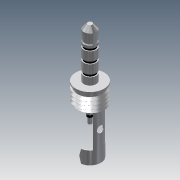
# Autodesk Inventor part: 3.5mm Plug
Saved by Autodesk Inventor 2013 SP2 (Build 170200200, 200)
## iProperties
Created: 2018-02-05
Part Number: 3.5mm Plug
Material: Generic
Document SubType Name: Modeling
Designer: ctouchatt
Density: 1 g/cm^3
Author: ctouchatt
Autodesk Inventor part; units mm, degrees
ref_plane "XZ Plane" through (0, 0, 0) normal (0, 1, 0) x (-1, 0, 0)
sketch "Sketch1" plane through (0, 0, 0) normal (0, 1, 0) x (-1, 0, 0)
  circle A0 centre (0, 0) radius 4.0005
  dimension "d0" = 8.001
  constraints: 1 centre point, 1 coincident
  measures "d0" diameter of A0
extrude "Extrusion1" add sketch "Sketch1" along normal blind 5.2832
sketch "Sketch2" plane through (0, 5.2832, 0) normal (0, 1, 0) x (1, 0, 0)
  circle A0 centre (0, 0) radius 4.0005 projected
  circle A1 centre (0, 0) radius 1.75
  dimension "d3" = 3.5
  constraints: 1 centre point, 1 coincident
  measures "d3" diameter of A1
extrude "Extrusion2" add sketch "Sketch2" along normal blind 14 contours A1
sketch "Sketch3" plane through (0, 0, 0) normal (0, 0, 1) x (1, 0, 0)
  line L0 (1.75, 19.2832) -> (-1.75, 19.2832) projected
  line L1 (-1.75, 5.2832) -> (1.75, 5.2832) projected
  line L2 (1.75, 5.2832) -> (1.75, 19.2832) projected
  line L3 (0, 19.2832) -> (0.635, 19.2832)
  line L4 (1.75, 19.2832) -> (1.75, 18.0132)
  line L5 (1.75, 18.0132) -> (0.635, 19.2832)
  line L6 (0, 19.2832) -> (0, 15.016)
  line L7 (0, 15.016) -> (1.75, 15.016) construction
  line L8 (1.75, 15.016) -> (1.5568, 15.236)
  line L9 (1.5568, 15.236) -> (1.75, 18.0132)
  line L10 (0, -3.8566) -> (0, 23.1398) projected
  line L11 (1.75, 14.3049) -> (1.496, 14.3049)
  line L12 (1.496, 14.3049) -> (1.496, 13.6699)
  line L13 (1.496, 13.6699) -> (1.75, 13.6699)
  line L14 (1.75, 13.6699) -> (1.75, 14.3049)
  line L15 (1.75, 11.1299) -> (1.496, 11.1299)
  line L16 (1.496, 11.1299) -> (1.496, 10.4949)
  line L17 (1.496, 10.4949) -> (1.75, 10.4949)
  line L18 (1.75, 10.4949) -> (1.75, 11.1299)
  line L19 (1.75, 7.9549) -> (1.496, 7.9549)
  line L20 (1.496, 7.9549) -> (1.496, 7.3199)
  line L21 (1.496, 7.3199) -> (1.75, 7.3199)
  line L22 (1.75, 7.3199) -> (1.75, 7.9549)
  line L23 (4.0005, 0) -> (4.0005, 5.2832) projected
  line L24 (-4.0005, 0) -> (4.0005, 0) projected
  line L25 (4.0005, 4.7772) -> (3.556, 4.7772)
  line L26 (3.556, 4.7772) -> (3.556, 3.7612)
  line L27 (3.556, 3.7612) -> (4.0005, 3.7612)
  line L28 (4.0005, 3.7612) -> (4.0005, 4.7772)
  point P0 (0, 0)
  dimension "d6" = 0.635
  dimension "d7" = 1.27
  dimension "d8" = 4.2672
  dimension "d11" = 0.254
  dimension "d12" = 0.635
  dimension "d15" = 0.254
  dimension "d16" = 0.635
  dimension "d17" = 2.54
  dimension "d18" = 4.9783
  dimension "d19" = 0.254
  dimension "d20" = 0.635
  dimension "d21" = 2.54
  dimension "d34" = 1.016
  dimension "d35" = 3.556
  constraints: 46 end point, 10 parallel, 5 horizontal, 4 perpendicular, 2 point on line, 1 midpoint, 6 other
  measures "d6" distance of L3.start L3.end
  measures "d7" distance of L4.start L4.end
  measures "d8" distance of L3.start L6.end
  measures "d11" distance of L13.end L12.end
  measures "d12" distance of L12.end L11.end
  measures "d15" distance of L17.end L16.end
  measures "d16" distance of L16.end L15.end
  measures "d17" distance between parallel lines of L13 L15
  measures "d18" distance between parallel lines of L0 L11
  measures "d19" distance of L21.end L20.end
  measures "d20" distance of L20.end L19.end
  measures "d21" distance between parallel lines of L17 L19
  measures "d34" distance of L25.end L26.end
  measures "d35" distance from line of point (0, 0) L26
revolve "Revolution1" cut sketch "Sketch3" angle 360 about axis through (0, -10, 0) along (0, 1, 0) contours L2 L5 L0 | L2 L8 L9 | L2 L13 L12 L11 | L2 L17 L16 L15 | L21 L20 L19 L2 | L27 L26 L25 L23
sketch "Sketch4" plane through (0, 0, 0) normal (0, -1, 0) x (1, 0, 0)
  circle A0 centre (0, 0) radius 4.0005 projected
  arc A1 (0, -3.048) -> (0, 3.048) centre (0, 0) ccw
  arc A2 (0, -2.794) -> (0, 2.794) centre (0, 0) ccw
  line L0 (0, 3.048) -> (0, 2.794)
  line L1 (0, -2.794) -> (0, -3.048)
  dimension "d22" = 6.096
  dimension "d23" = 5.588
  constraints: 4 end point, 4 point on circle, 2 centre point, 2 coincident, 1 collinear, 1 vertical
  measures "d22" diameter of A1
  measures "d23" diameter of A2
extrude "Extrusion3" add sketch "Sketch4" along normal blind 13.335 contours L1 A2 L0 A1
ref_plane "Work Plane1" through (0, 0, 3.048) normal (0, 0, 1) x (1, 0, 0)
sketch "Sketch5" plane through (0, 0, 3.048) normal (0, 0, 1) x (1, 0, 0)
  line L0 (0, 0) -> (0, 0) projected
  line L1 (0, 0) -> (0, -13.335) projected
  line L2 (0, -13.335) -> (0, -13.335) projected
  line L3 (0, 0) -> (0, -13.335) projected
  line L4 (0, -13.335) -> (3.048, -13.335) projected
  line L5 (2.794, -13.335) -> (2.794, 0) projected
  line L6 (3.048, 0) -> (3.048, -13.335) projected
  line L7 (0.49, -9.7028) -> (2.54, -9.7028)
  line L8 (2.54, -9.7028) -> (2.54, 0)
  line L9 (2.54, 0) -> (0, 0)
  line L10 (0, 0) -> (0, -9.7028)
  line L11 (0, -11.5314) -> (0.49, -9.7028)
  line L12 (0, -11.5314) -> (1.8931, -11.5314) construction
  line L13 (0, -11.5314) -> (0.4833, -13.335)
  line L14 (0, -11.5314) -> (1.8672, -11.5314) construction
  line L15 (0, -9.7028) -> (0, -13.335)
  line L16 (0, -13.335) -> (0.4833, -13.335)
  dimension "d26" = 2.54
  dimension "d28" = 3.6322
  dimension "d29" = 75
  dimension "d30" = 75
  constraints: 20 end point, 3 horizontal, 3 point on line, 2 equal length, 2 parallel, 2 perpendicular, 1 collinear
  measures "d26" distance of L10.end L7.end
  measures "d28" distance between parallel lines of L7 L4
  measures "d29" angle of L12 L11
  measures "d30" angle of L13 L14
extrude "Extrusion4" cut sketch "Sketch5" against normal through all
sketch "Sketch6" plane through (0, 0, 0) normal (0, 0, 1) x (1, 0, 0)
  line L0 (4.0005, 0) -> (4.0005, 3.7612) projected
  line L1 (-4.0005, 0) -> (4.0005, 0) projected
  line L2 (4.0005, 0) -> (4.0005, -1)
  line L3 (4.0005, -1) -> (3.1345, -0.5)
  line L4 (3.1345, -0.5) -> (4.0005, 0)
  point P0 (0, 0)
  dimension "d36" = 1
  dimension "d37" = 60
  constraints: 6 end point, 1 perpendicular
  measures "d36" distance of L0.start L2.end
  measures "d37" angle of L2 L3
coil "Coil1" sketch "Sketch6" operation cut axis through (0, -10, 0) along (0, 1, 0) pitch 1.0254 turns 4.458748 hand right
sketch "Sketch7" plane through (0, 0, 0) normal (0, -1, 0) x (1, 0, 0)
  arc A0 (2.54, -1.164) -> (2.54, 1.164) centre (0, 0) ccw projected
  line L0 (2.54, 1.6848) -> (2.54, 1.164) projected
  arc A1 (2.54, -1.6848) -> (2.54, 1.6848) centre (0, 0) ccw projected
  line L1 (2.54, -1.164) -> (2.54, -1.6848) projected
  arc A2 (4.0005, 0) -> (3.9521, 0.6201) centre (0, 0) ccw projected
  circle A3 centre (0, 0) radius 3.048
  constraints: 1 centre point, 1 coincident, 1 concentric
extrude "Extrusion5" add sketch "Sketch7" along normal blind 0.0254 contours L1 A3 L0 A0
sketch "Sketch8" plane through (0, -0.0254, 0) normal (0, -1, 0) x (1, 0, 0)
  arc A0 (2.54, -1.164) -> (2.54, 1.164) centre (0, 0) ccw projected
  circle A1 centre (0, 0) radius 0.9144
  dimension "d48" = 1.8288
  constraints: 1 centre point, 1 coincident
  measures "d48" diameter of A1
extrude "Extrusion6" add sketch "Sketch8" along normal blind 2.54
sketch "Sketch9" plane through (0, -2.5654, 0) normal (0, -1, 0) x (1, 0, 0)
  circle A0 centre (0, 0) radius 0.9144 projected
  circle A1 centre (0, 0) radius 0.7582
  constraints: 1 centre point, 1 coincident
extrude "Extrusion7" add sketch "Sketch9" along normal blind 0.762 contours A1
sketch "Sketch10" plane through (0, -3.3274, 0) normal (0, -1, 0) x (1, 0, 0)
  circle A0 centre (0, 0) radius 0.7582 projected
  circle A1 centre (0, 0) radius 0.5207
  dimension "d53" = 1.0414
  constraints: 1 centre point, 1 coincident
  measures "d53" diameter of A1
extrude "Extrusion8" add sketch "Sketch10" along normal blind 1.778 contours A1
sketch "Sketch11" plane through (0, 0, 0) normal (1, 0, 0) x (0, 1, 0)
  line L0 (0, -1.0852) -> (-4.973, -3.0087)
  line L1 (-4.973, -3.0087) -> (-4.8631, -3.293)
  line L2 (-0.0254, 3.048) -> (-0.0254, -3.048) projected
  line L3 (-4.8631, -3.293) -> (-0.0254, -1.4219)
  line L4 (-0.0254, -1.4219) -> (-0.0254, -1.0951)
  point P0 (0, 0)
  point P1 (-0.0254, 1.6848)
  point P2 (-0.0254, -1.6848)
  dimension "d56" = 0.3048
  constraints: 8 end point, 3 point on line, 2 perpendicular
  measures "d56" distance of L0.end L1.end
extrude "Extrusion9" add sketch "Sketch11" along normal mid plane 0.8382
ref_plane "Work Plane2" through (3.048, 0, 0) normal (1, 0, 0) x (0, 1, 0)
sketch "Sketch13" plane through (3.048, 0, 0) normal (1, 0, 0) x (0, 1, 0)
  line L0 (-13.335, 3.0094) -> (-13.335, -3.0094) projected
  point P0 (0, 0)
  point P1 (-5.08, 0)
  dimension "d67" = 8.255
  measures "d67" distance from line of L0 point (-5.08, 0)
hole "Hole2" at (3.048, -5.08, 0) direction (-1, 0, 0) diameter 1.905 depth 1.27 tip angle 118
body "Solid1"
